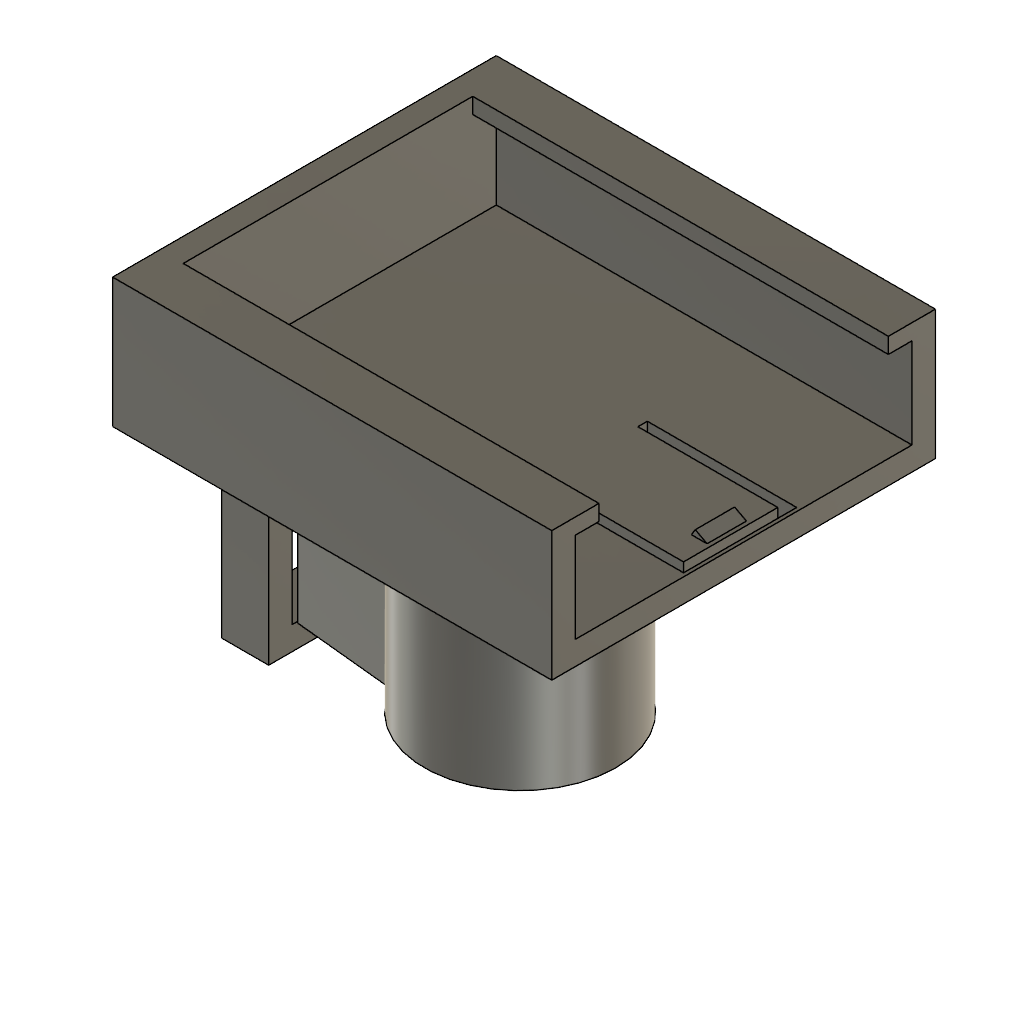
veebikaamera-post-v2-ulemine (Autodesk Fusion 360 design; units mm, degrees)
part number: 2026-10-25-11-18-53-740
part number: 2026-10-25-11-18-54-031
part number: 2026-10-25-11-18-54-931
Autodesk Fusion 360 part; units mm, degrees
ref_plane "WorkPlane1" through (0, 0, 0) normal (0, 0, 1) x (1, 0, 0) in component "webcam_top"
sketch "slot_body" plane through (0, 0, 0) normal (0, 0, 1) x (1, 0, 0) in component "webcam_top"
  line L0 (-27.45, -24.42) -> (28.45, -24.42)
  line L1 (28.45, -24.42) -> (28.45, 24.42)
  line L2 (28.45, 24.42) -> (-27.45, 24.42)
  line L3 (-27.45, 24.42) -> (-27.45, -24.42)
extrude "slot_body (1)" add sketch "slot_body" along normal blind 16.48 makes body 1 in component "webcam_top"
ref_plane "WorkPlane2" through (0, 0, 3) normal (0, 0, 1) x (1, 0, 0) in component "webcam_top"
sketch "slot_cavity" plane through (0, 0, 3) normal (0, 0, 1) x (1, 0, 0) in component "webcam_top"
  line L0 (-24.45, -21.42) -> (29.45, -21.42)
  line L1 (29.45, -21.42) -> (29.45, 21.42)
  line L2 (29.45, 21.42) -> (-24.45, 21.42)
  line L3 (-24.45, 21.42) -> (-24.45, -21.42)
extrude "slot_cavity (1)" cut sketch "slot_cavity" along normal blind 11.48 bodies 1 in component "webcam_top"
ref_plane "WorkPlane3" through (0, 0, 14.38) normal (0, 0, 1) x (1, 0, 0) in component "webcam_top"
sketch "slot_top_open" plane through (0, 0, 14.38) normal (0, 0, 1) x (1, 0, 0) in component "webcam_top"
  line L0 (-24.45, -18.42) -> (29.45, -18.42)
  line L1 (29.45, -18.42) -> (29.45, 18.42)
  line L2 (29.45, 18.42) -> (-24.45, 18.42)
  line L3 (-24.45, 18.42) -> (-24.45, -18.42)
extrude "slot_top_open (1)" cut sketch "slot_top_open" along normal blind 3.1 bodies 1 in component "webcam_top"
ref_plane "WorkPlane4" through (0, 0, -30) normal (0, 0, 1) x (1, 0, 0) in component "webcam_top"
sketch "collar" plane through (0, 0, -30) normal (0, 0, 1) x (1, 0, 0) in component "webcam_top"
  circle A0 centre (0, 0) radius 12.2
extrude "collar (1)" add sketch "collar" along normal blind 30 bodies 1 in component "webcam_top"
ref_plane "WorkPlane5" through (0, 0, -30) normal (0, 0, 1) x (1, 0, 0) in component "webcam_top"
sketch "clamp_tabs" plane through (0, 0, -30) normal (0, 0, 1) x (1, 0, 0) in component "webcam_top"
  line L0 (-10, -5.7) -> (-24, -4.3)
  line L1 (-24, -4.3) -> (-24, 4.3)
  line L2 (-24, 4.3) -> (-10, 5.7)
  line L3 (-10, 5.7) -> (-10, -5.7)
extrude "clamp_tabs (1)" add sketch "clamp_tabs" along normal blind 20 bodies 1 in component "webcam_top"
ref_plane "WorkPlane6" through (0, 0, -31) normal (0, 0, 1) x (1, 0, 0) in component "webcam_top"
sketch "bore" plane through (0, 0, -31) normal (0, 0, 1) x (1, 0, 0) in component "webcam_top"
  circle A0 centre (0, 0) radius 8.2
extrude "bore (1)" cut sketch "bore" along normal blind 31 bodies 1 in component "webcam_top"
ref_plane "WorkPlane7" through (0, 0, -31) normal (0, 0, 1) x (1, 0, 0) in component "webcam_top"
sketch "slit" plane through (0, 0, -31) normal (0, 0, 1) x (1, 0, 0) in component "webcam_top"
  line L0 (-25, -1) -> (-7.2, -1)
  line L1 (-7.2, -1) -> (-7.2, 1)
  line L2 (-7.2, 1) -> (-25, 1)
  line L3 (-25, 1) -> (-25, -1)
extrude "slit (1)" cut sketch "slit" along normal blind 23 bodies 1 in component "webcam_top"
ref_plane "WorkPlane8" through (0, 0, -9.5) normal (0, 0, 1) x (1, 0, 0) in component "webcam_top"
sketch "relief_kerf" plane through (0, 0, -9.5) normal (0, 0, 1) x (1, 0, 0) in component "webcam_top"
  line L0 (-13.2, -13.2) -> (1, -13.2)
  line L1 (1, -13.2) -> (1, 13.2)
  line L2 (1, 13.2) -> (-13.2, 13.2)
  line L3 (-13.2, 13.2) -> (-13.2, -13.2)
extrude "relief_kerf (1)" cut sketch "relief_kerf" along normal blind 1.5 bodies 1 in component "webcam_top"
ref_plane "WorkPlane9" through (0, 0, -1) normal (0, 0, 1) x (1, 0, 0) in component "webcam_top"
sketch "tongue_cut" plane through (0, 0, -1) normal (0, 0, 1) x (1, 0, 0) in component "webcam_top"
  line L0 (9, 7.2) -> (28, 7.2)
  line L1 (28, 7.2) -> (28, -7.2)
  line L2 (28, -7.2) -> (9, -7.2)
  line L3 (9, -7.2) -> (9, -6)
  line L4 (9, -6) -> (26.8, -6)
  line L5 (26.8, -6) -> (26.8, 6)
  line L6 (26.8, 6) -> (9, 6)
  line L7 (9, 6) -> (9, 7.2)
extrude "tongue_cut (1)" cut sketch "tongue_cut" along normal blind 5 bodies 1 in component "webcam_top"
ref_plane "WorkPlane10" through (0, 0, -1) normal (0, 0, 1) x (1, 0, 0) in component "webcam_top"
sketch "tongue_thin" plane through (0, 0, -1) normal (0, 0, 1) x (1, 0, 0) in component "webcam_top"
  line L0 (9, -6) -> (26.8, -6)
  line L1 (26.8, -6) -> (26.8, 6)
  line L2 (26.8, 6) -> (9, 6)
  line L3 (9, 6) -> (9, -6)
extrude "tongue_thin (1)" cut sketch "tongue_thin" along normal blind 2.5 bodies 1 in component "webcam_top"
sketch "bump" plane through (0, 0, 0) normal (0, 1, 0) x (1, 0, 0) in component "webcam_top"
  line L0 (24.3, -3) -> (24.8, -3.8)
  line L1 (24.8, -3.8) -> (26.3, -3)
  line L2 (26.3, -3) -> (24.3, -3)
extrude "bump (1)" add sketch "bump" along normal mid plane 5 bodies 1 in component "webcam_top"
ref_plane "WorkPlane1" through (0, 0, -33.3) normal (0, 0, 1) x (1, 0, 0) in component "wedge_ring"
sketch "ring_outer" plane through (0, 0, -33.3) normal (0, 0, 1) x (1, 0, 0) in component "wedge_ring"
  line L0 (-30.5, -7.5) -> (-24.5, -7.5)
  line L1 (-24.5, -7.5) -> (-24.5, 7.5)
  line L2 (-24.5, 7.5) -> (-30.5, 7.5)
  line L3 (-30.5, 7.5) -> (-30.5, -7.5)
extrude "ring_outer (1)" add sketch "ring_outer" along normal blind 26.6 separate body makes body 2 in component "wedge_ring"
ref_plane "WorkPlane2" through (0, 0, -30.3) normal (0, 0, 1) x (1, 0, 0) in component "wedge_ring"
sketch "ring_window" plane through (0, 0, -30.3) normal (0, 0, 1) x (1, 0, 0) in component "wedge_ring"
  line L0 (-31.5, -4.5) -> (-23.5, -4.5)
  line L1 (-23.5, -4.5) -> (-23.5, 4.5)
  line L2 (-23.5, 4.5) -> (-31.5, 4.5)
  line L3 (-31.5, 4.5) -> (-31.5, -4.5)
extrude "ring_window (1)" cut sketch "ring_window" along normal blind 20.6 bodies 2 in component "wedge_ring"
ref_plane "WorkPlane11" through (0, 0, -31) normal (0, 0, 1) x (1, 0, 0) in component "webcam_top"
sketch "bore_teardrop" plane through (0, 0, -31) normal (0, 0, 1) x (1, 0, 0) in component "webcam_top"
  line L0 (-5.7983, 5.7983) -> (-11.5966, 0)
  line L1 (-11.5966, 0) -> (-5.7983, -5.7983)
  line L2 (-5.7983, -5.7983) -> (-5.7983, 5.7983)
extrude "bore_teardrop (1)" [suppressed] in component "webcam_top"
ref_plane "WorkPlane12" through (0, 0, -31) normal (0, 0, 1) x (1, 0, 0) in component "webcam_top"
sketch "bore_teardrop_up" plane through (0, 0, -31) normal (0, 0, 1) x (1, 0, 0) in component "webcam_top"
  line L0 (5.7983, 5.7983) -> (11.5966, 0)
  line L1 (11.5966, 0) -> (5.7983, -5.7983)
  line L2 (5.7983, -5.7983) -> (5.7983, 5.7983)
extrude "bore_teardrop_up_cut" cut sketch "bore_teardrop_up" along normal blind 31 bodies 1 in component "webcam_top"
component "webcam_top" placed x (1, 0, 0) y (0, 1, 0) z (0, 0, 1) at (0, 0, 0)
component "wedge_ring" placed x (1, 0, 0) y (0, 1, 0) z (0, 0, 1) at (0, 0, 0)
equation "pipe_d = 16 mm" comment "Vertical pipe OD (rig doc 16 mm; caliper TODO)"
equation "bore_clr = 0.2 mm" comment "Bore clearance per side; v4 elbow with 0.2 fitted well (Denys 25.10)"
equation "collar_wall = 4 mm" comment "Collar wall"
equation "collar_len = 30 mm" comment "Collar length on the pipe"
equation "slit_w = 2 mm" comment "Collar slit width"
equation "kerf_z = 8 mm" comment "Depth of the relief cut below the floor: the collar under it clamps"
equation "kerf_w = 1.5 mm" comment "Relief cut height"
equation "tab_len = 20 mm" comment "Clamp tab height"
equation "tab_root_w = 11.4 mm" comment "Both tabs + slit, width at x = -10"
equation "tab_tip_w = 8.6 mm" comment "Width at the tab tip x = -24 (taper ~5.7 deg per side, self-locking)"
equation "tab_tip_x = 24 mm" comment "Tab tip distance from the pipe axis"
equation "ring_win_w = 9 mm" comment "Wedge ring window width: free at the tip, squeezes ~1.3 mm when pushed in to x -16"
equation "ring_bar = 3 mm" comment "Wedge ring bar thickness"
equation "ring_depth = 6 mm" comment "Wedge ring depth along the tabs"
equation "ring_clr = 0.3 mm" comment "Wedge ring window clearance in Z"
equation "clip_w = 42.04 mm" comment "AWC-03 clip lower leaf, hinge side (caliper, Denys 23.10)"
equation "clip_l = 48.5 mm" comment "AWC-03 clip lower leaf length (caliper)"
equation "clip_t = 10.88 mm" comment "AWC-03 clip lower leaf thickness (caliper)"
equation "slot_clr_w = 0.4 mm" comment "Slot clearance per side in width (Lab 1: 0.4 slides, 0.2 jams)"
equation "slot_clr_l = 0.4 mm" comment "Slot extra length"
equation "slot_clr_t = 0.6 mm" comment "Slot clearance in thickness"
equation "floor_t = 3 mm" comment "Slot floor"
equation "side_wall = 3 mm" comment "Slot side and back walls"
equation "lip_t = 2 mm" comment "Lip thickness over the leaf"
equation "lip_over = 3 mm" comment "Lip overlap over the leaf edge per side"
equation "entry_ext = 4 mm" comment "Floor/walls beyond the leaf trailing edge (carries the snap bump)"
equation "tongue_t = 1.5 mm" comment "Snap tongue thickness (Lab 1 flex piece: 1.5 mm springs back)"
equation "tongue_w = 12 mm" comment "Snap tongue width"
equation "tongue_gap = 1.2 mm" comment "Cut around the snap tongue"
equation "bump_h = 0.8 mm" comment "Snap bump height"
named bodies: "webcam_top", "wedge_ring"
